Autodesk Fusion 360 part; units mm, degrees
(part 7 of 7)
equation "d681 = spokeDepth"
equation "d683 = bodyWidth"
equation "d684 = bodyLength"
equation "d687 = rootRadius"
equation "d688 = qFrontBack"
equation "d690 = rearCarrierClearance"
equation "d691 = spokeDepth"
equation "d693 = qFront"
equation "d695 = raceRelief"
equation "d696 = frontSeatDepth + shoulder"
equation "d698 = qFront"
equation "d700 = seatDiameter"
equation "d701 = frontSeatDepth"
equation "d703 = qFront"
equation "d705 = supportCircle / 2"
equation "d706 = m3Clearance"
equation "d707 = frontSeatDepth + shoulder"
equation "d711 = qFront"
equation "d713 = coreOD"
equation "d714 = entryChamfer"
equation "d715 = bodyWidth / 2"
equation "d717 = abs(( 16 mm + ( -6.5 mm ) ) / sqrt(2))"
equation "d718 = abs(( 16 mm - ( -6.5 mm ) ) / sqrt(2))"
equation "d720 = abs(( 16 mm + ( 6.5 mm ) ) / sqrt(2))"
equation "d721 = abs(( 16 mm - ( 6.5 mm ) ) / sqrt(2))"
equation "d723 = -( bodyWidth / 2 )"
equation "d725 = -qFront"
equation "d727 = mountOD"
equation "d728 = -( -qFront - hubFace )"
equation "d730 = -qFront"
equation "d732 = abs(( 0 mm ) * ( cos(-73.6750500631048 deg) ) - ( -1 ) * spokeWidth / 2 * ( sin(-73.6750500631048 deg) ))"
equation "d733 = abs(( 0 mm ) * ( sin(-73.6750500631048 deg) ) + ( -1 ) * spokeWidth / 2 * ( cos(-73.6750500631048 deg) ))"
equation "d734 = abs(( bodyWidth ) * ( cos(-73.6750500631048 deg) ) - ( -1 ) * spokeWidth / 2 * ( sin(-73.6750500631048 deg) ))"
equation "d735 = abs(( bodyWidth ) * ( sin(-73.6750500631048 deg) ) + ( -1 ) * spokeWidth / 2 * ( cos(-73.6750500631048 deg) ))"
equation "d736 = abs(( bodyWidth ) * ( cos(-73.6750500631048 deg) ) - ( 1 ) * spokeWidth / 2 * ( sin(-73.6750500631048 deg) ))"
equation "d737 = abs(( bodyWidth ) * ( sin(-73.6750500631048 deg) ) + ( 1 ) * spokeWidth / 2 * ( cos(-73.6750500631048 deg) ))"
equation "d738 = abs(( 0 mm ) * ( cos(-73.6750500631048 deg) ) - ( 1 ) * spokeWidth / 2 * ( sin(-73.6750500631048 deg) ))"
equation "d739 = abs(( 0 mm ) * ( sin(-73.6750500631048 deg) ) + ( 1 ) * spokeWidth / 2 * ( cos(-73.6750500631048 deg) ))"
equation "d740 = -( spokeDepth )"
equation "d742 = abs(( 0 mm ) * ( cos(-30.3611934048217 deg) ) - ( -1 ) * spokeWidth / 2 * ( sin(-30.3611934048217 deg) ))"
equation "d743 = abs(( 0 mm ) * ( sin(-30.3611934048217 deg) ) + ( -1 ) * spokeWidth / 2 * ( cos(-30.3611934048217 deg) ))"
equation "d744 = abs(( bodyWidth ) * ( cos(-30.3611934048217 deg) ) - ( -1 ) * spokeWidth / 2 * ( sin(-30.3611934048217 deg) ))"
equation "d745 = abs(( bodyWidth ) * ( sin(-30.3611934048217 deg) ) + ( -1 ) * spokeWidth / 2 * ( cos(-30.3611934048217 deg) ))"
equation "d746 = abs(( bodyWidth ) * ( cos(-30.3611934048217 deg) ) - ( 1 ) * spokeWidth / 2 * ( sin(-30.3611934048217 deg) ))"
equation "d747 = abs(( bodyWidth ) * ( sin(-30.3611934048217 deg) ) + ( 1 ) * spokeWidth / 2 * ( cos(-30.3611934048217 deg) ))"
equation "d748 = abs(( 0 mm ) * ( cos(-30.3611934048217 deg) ) - ( 1 ) * spokeWidth / 2 * ( sin(-30.3611934048217 deg) ))"
equation "d749 = abs(( 0 mm ) * ( sin(-30.3611934048217 deg) ) + ( 1 ) * spokeWidth / 2 * ( cos(-30.3611934048217 deg) ))"
equation "d750 = -( spokeDepth )"
equation "d752 = abs(( 0 mm ) * ( cos(30.3611934048217 deg) ) - ( -1 ) * spokeWidth / 2 * ( sin(30.3611934048217 deg) ))"
equation "d753 = abs(( 0 mm ) * ( sin(30.3611934048217 deg) ) + ( -1 ) * spokeWidth / 2 * ( cos(30.3611934048217 deg) ))"
equation "d754 = abs(( bodyWidth ) * ( cos(30.3611934048217 deg) ) - ( -1 ) * spokeWidth / 2 * ( sin(30.3611934048217 deg) ))"
equation "d755 = abs(( bodyWidth ) * ( sin(30.3611934048217 deg) ) + ( -1 ) * spokeWidth / 2 * ( cos(30.3611934048217 deg) ))"
equation "d756 = abs(( bodyWidth ) * ( cos(30.3611934048217 deg) ) - ( 1 ) * spokeWidth / 2 * ( sin(30.3611934048217 deg) ))"
equation "d757 = abs(( bodyWidth ) * ( sin(30.3611934048217 deg) ) + ( 1 ) * spokeWidth / 2 * ( cos(30.3611934048217 deg) ))"
equation "d758 = abs(( 0 mm ) * ( cos(30.3611934048217 deg) ) - ( 1 ) * spokeWidth / 2 * ( sin(30.3611934048217 deg) ))"
equation "d759 = abs(( 0 mm ) * ( sin(30.3611934048217 deg) ) + ( 1 ) * spokeWidth / 2 * ( cos(30.3611934048217 deg) ))"
equation "d760 = -( spokeDepth )"
equation "d762 = abs(( 0 mm ) * ( cos(73.6750500631048 deg) ) - ( -1 ) * spokeWidth / 2 * ( sin(73.6750500631048 deg) ))"
equation "d763 = abs(( 0 mm ) * ( sin(73.6750500631048 deg) ) + ( -1 ) * spokeWidth / 2 * ( cos(73.6750500631048 deg) ))"
equation "d764 = abs(( bodyWidth ) * ( cos(73.6750500631048 deg) ) - ( -1 ) * spokeWidth / 2 * ( sin(73.6750500631048 deg) ))"
equation "d765 = abs(( bodyWidth ) * ( sin(73.6750500631048 deg) ) + ( -1 ) * spokeWidth / 2 * ( cos(73.6750500631048 deg) ))"
equation "d766 = abs(( bodyWidth ) * ( cos(73.6750500631048 deg) ) - ( 1 ) * spokeWidth / 2 * ( sin(73.6750500631048 deg) ))"
equation "d767 = abs(( bodyWidth ) * ( sin(73.6750500631048 deg) ) + ( 1 ) * spokeWidth / 2 * ( cos(73.6750500631048 deg) ))"
equation "d768 = abs(( 0 mm ) * ( cos(73.6750500631048 deg) ) - ( 1 ) * spokeWidth / 2 * ( sin(73.6750500631048 deg) ))"
equation "d769 = abs(( 0 mm ) * ( sin(73.6750500631048 deg) ) + ( 1 ) * spokeWidth / 2 * ( cos(73.6750500631048 deg) ))"
equation "d770 = -( spokeDepth )"
equation "d772 = abs(( 0 mm ) * ( cos(106.324949936895 deg) ) - ( -1 ) * spokeWidth / 2 * ( sin(106.324949936895 deg) ))"
equation "d773 = abs(( 0 mm ) * ( sin(106.324949936895 deg) ) + ( -1 ) * spokeWidth / 2 * ( cos(106.324949936895 deg) ))"
equation "d774 = abs(( bodyWidth ) * ( cos(106.324949936895 deg) ) - ( -1 ) * spokeWidth / 2 * ( sin(106.324949936895 deg) ))"
equation "d775 = abs(( bodyWidth ) * ( sin(106.324949936895 deg) ) + ( -1 ) * spokeWidth / 2 * ( cos(106.324949936895 deg) ))"
equation "d776 = abs(( bodyWidth ) * ( cos(106.324949936895 deg) ) - ( 1 ) * spokeWidth / 2 * ( sin(106.324949936895 deg) ))"
equation "d777 = abs(( bodyWidth ) * ( sin(106.324949936895 deg) ) + ( 1 ) * spokeWidth / 2 * ( cos(106.324949936895 deg) ))"
equation "d778 = abs(( 0 mm ) * ( cos(106.324949936895 deg) ) - ( 1 ) * spokeWidth / 2 * ( sin(106.324949936895 deg) ))"
equation "d779 = abs(( 0 mm ) * ( sin(106.324949936895 deg) ) + ( 1 ) * spokeWidth / 2 * ( cos(106.324949936895 deg) ))"
equation "d780 = -( spokeDepth )"
equation "d782 = abs(( 0 mm ) * ( cos(149.638806595178 deg) ) - ( -1 ) * spokeWidth / 2 * ( sin(149.638806595178 deg) ))"
equation "d783 = abs(( 0 mm ) * ( sin(149.638806595178 deg) ) + ( -1 ) * spokeWidth / 2 * ( cos(149.638806595178 deg) ))"
equation "d784 = abs(( bodyWidth ) * ( cos(149.638806595178 deg) ) - ( -1 ) * spokeWidth / 2 * ( sin(149.638806595178 deg) ))"
equation "d785 = abs(( bodyWidth ) * ( sin(149.638806595178 deg) ) + ( -1 ) * spokeWidth / 2 * ( cos(149.638806595178 deg) ))"
equation "d786 = abs(( bodyWidth ) * ( cos(149.638806595178 deg) ) - ( 1 ) * spokeWidth / 2 * ( sin(149.638806595178 deg) ))"
equation "d787 = abs(( bodyWidth ) * ( sin(149.638806595178 deg) ) + ( 1 ) * spokeWidth / 2 * ( cos(149.638806595178 deg) ))"
equation "d788 = abs(( 0 mm ) * ( cos(149.638806595178 deg) ) - ( 1 ) * spokeWidth / 2 * ( sin(149.638806595178 deg) ))"
equation "d789 = abs(( 0 mm ) * ( sin(149.638806595178 deg) ) + ( 1 ) * spokeWidth / 2 * ( cos(149.638806595178 deg) ))"
equation "d790 = -( spokeDepth )"
equation "d792 = abs(( 0 mm ) * ( cos(-149.638806595178 deg) ) - ( -1 ) * spokeWidth / 2 * ( sin(-149.638806595178 deg) ))"
equation "d793 = abs(( 0 mm ) * ( sin(-149.638806595178 deg) ) + ( -1 ) * spokeWidth / 2 * ( cos(-149.638806595178 deg) ))"
equation "d794 = abs(( bodyWidth ) * ( cos(-149.638806595178 deg) ) - ( -1 ) * spokeWidth / 2 * ( sin(-149.638806595178 deg) ))"
equation "d795 = abs(( bodyWidth ) * ( sin(-149.638806595178 deg) ) + ( -1 ) * spokeWidth / 2 * ( cos(-149.638806595178 deg) ))"
equation "d796 = abs(( bodyWidth ) * ( cos(-149.638806595178 deg) ) - ( 1 ) * spokeWidth / 2 * ( sin(-149.638806595178 deg) ))"
equation "d797 = abs(( bodyWidth ) * ( sin(-149.638806595178 deg) ) + ( 1 ) * spokeWidth / 2 * ( cos(-149.638806595178 deg) ))"
equation "d798 = abs(( 0 mm ) * ( cos(-149.638806595178 deg) ) - ( 1 ) * spokeWidth / 2 * ( sin(-149.638806595178 deg) ))"
equation "d799 = abs(( 0 mm ) * ( sin(-149.638806595178 deg) ) + ( 1 ) * spokeWidth / 2 * ( cos(-149.638806595178 deg) ))"
equation "d800 = -( spokeDepth )"
equation "d802 = abs(( 0 mm ) * ( cos(-106.324949936895 deg) ) - ( -1 ) * spokeWidth / 2 * ( sin(-106.324949936895 deg) ))"
equation "d803 = abs(( 0 mm ) * ( sin(-106.324949936895 deg) ) + ( -1 ) * spokeWidth / 2 * ( cos(-106.324949936895 deg) ))"
equation "d804 = abs(( bodyWidth ) * ( cos(-106.324949936895 deg) ) - ( -1 ) * spokeWidth / 2 * ( sin(-106.324949936895 deg) ))"
equation "d805 = abs(( bodyWidth ) * ( sin(-106.324949936895 deg) ) + ( -1 ) * spokeWidth / 2 * ( cos(-106.324949936895 deg) ))"
equation "d806 = abs(( bodyWidth ) * ( cos(-106.324949936895 deg) ) - ( 1 ) * spokeWidth / 2 * ( sin(-106.324949936895 deg) ))"
equation "d807 = abs(( bodyWidth ) * ( sin(-106.324949936895 deg) ) + ( 1 ) * spokeWidth / 2 * ( cos(-106.324949936895 deg) ))"
equation "d808 = abs(( 0 mm ) * ( cos(-106.324949936895 deg) ) - ( 1 ) * spokeWidth / 2 * ( sin(-106.324949936895 deg) ))"
equation "d809 = abs(( 0 mm ) * ( sin(-106.324949936895 deg) ) + ( 1 ) * spokeWidth / 2 * ( cos(-106.324949936895 deg) ))"
equation "d810 = -( spokeDepth )"
equation "d812 = bodyWidth"
equation "d813 = bodyLength"
equation "d816 = rootRadius"
equation "d817 = -qFront"
equation "d819 = mountOpening"
equation "d820 = -( -qFront - hubFace )"
equation "d822 = -qFront"
equation "d824 = abs(mountCircle / ( 2 * sqrt(2) ))"
equation "d825 = abs(mountCircle / ( 2 * sqrt(2) ))"
equation "d826 = m4Clearance"
equation "d827 = abs(-mountCircle / ( 2 * sqrt(2) ))"
equation "d828 = abs(mountCircle / ( 2 * sqrt(2) ))"
equation "d829 = m4Clearance"
equation "d830 = abs(-mountCircle / ( 2 * sqrt(2) ))"
equation "d831 = abs(-mountCircle / ( 2 * sqrt(2) ))"
equation "d832 = m4Clearance"
equation "d833 = abs(mountCircle / ( 2 * sqrt(2) ))"
equation "d834 = abs(-mountCircle / ( 2 * sqrt(2) ))"
equation "d835 = m4Clearance"
equation "d836 = -( -qFront - hubFace )"
equation "d838 = abs(mountCircle / ( 2 * sqrt(2) ))"
equation "d839 = abs(mountCircle / ( 2 * sqrt(2) ))"
equation "d840 = 2 * ( nutAF ) / sqrt(3)"
equation "d841 = -( nutDepth )"
equation "d843 = abs(-mountCircle / ( 2 * sqrt(2) ))"
equation "d844 = abs(mountCircle / ( 2 * sqrt(2) ))"
equation "d845 = 2 * ( nutAF ) / sqrt(3)"
equation "d846 = -( nutDepth )"
equation "d848 = abs(-mountCircle / ( 2 * sqrt(2) ))"
equation "d849 = abs(-mountCircle / ( 2 * sqrt(2) ))"
equation "d850 = 2 * ( nutAF ) / sqrt(3)"
equation "d851 = -( nutDepth )"
equation "d853 = abs(mountCircle / ( 2 * sqrt(2) ))"
equation "d854 = abs(-mountCircle / ( 2 * sqrt(2) ))"
equation "d855 = 2 * ( nutAF ) / sqrt(3)"
equation "d856 = -( nutDepth )"
equation "d858 = abs(( -8 mm - 13 mm ) / sqrt(2))"
equation "d859 = abs(( -8 mm + 13 mm ) / sqrt(2))"
equation "d860 = abs(( -30 mm - 13 mm ) / sqrt(2))"
equation "d861 = abs(( -30 mm + 13 mm ) / sqrt(2))"
equation "d862 = abs(( -30 mm + 13 mm ) / sqrt(2))"
equation "d863 = abs(( -30 mm - 13 mm ) / sqrt(2))"
equation "d864 = abs(( -8 mm + 13 mm ) / sqrt(2))"
equation "d865 = abs(( -8 mm - 13 mm ) / sqrt(2))"
equation "d866 = mountOD"
equation "d868 = bedRelief"
equation "d869 = tubeCornerChamfer"
equation "d870 = tubeRimChamfer"
equation "d873 = bodyWidth / 2"
equation "d875 = abs(( 1 ) * ( ( 1 ) * cordStation ) + ( 0 ) * ( 0 mm ))"
equation "d877 = -( wall )"
equation "d879 = bedRelief"
equation "d882 = bodyWidth / 2"
equation "d884 = abs(( -1 ) * ( ( 1 ) * cordStation ) + ( 0 ) * ( 0 mm ))"
equation "d886 = -( wall )"
equation "d888 = bedRelief"
equation "d889 = bedRelief"
equation "d890 = tubeCornerChamfer"
equation "d891 = tubeRimChamfer"
equation "d894 = bodyWidth / 2"
equation "d896 = abs(( 1 ) * ( ( -1 ) * cordStation ) + ( 0 ) * ( 0 mm ))"
equation "d898 = -( wall )"
equation "d900 = bedRelief"
equation "d903 = bodyWidth / 2"
equation "d905 = abs(( -1 ) * ( ( -1 ) * cordStation ) + ( 0 ) * ( 0 mm ))"
equation "d907 = -( wall )"
equation "d909 = bedRelief"
equation "d910 = qRearBase"
equation "d912 = coreOD"
equation "d913 = shoulder + rearSeatDepth"
equation "d915 = qRearBase"
equation "d917 = raceRelief"
equation "d918 = shoulder + rearSeatDepth"
equation "d920 = qRearBearing"
equation "d922 = seatDiameter"
equation "d923 = rearSeatDepth"
equation "d925 = qRearBase"
equation "d927 = supportCircle / 2"
equation "d928 = m3Clearance"
equation "d929 = shoulder + rearSeatDepth"
equation "d933 = entryChamfer"
equation "d934 = bedRelief"
equation "d935 = qFront - capThickness"
equation "d937 = coreOD"
equation "d938 = raceRelief"
equation "d939 = capThickness"
equation "d941 = qFront - capThickness"
equation "d943 = supportCircle / 2"
equation "d944 = m3Clearance"
equation "d945 = capThickness"
equation "d949 = bedRelief"
equation "d950 = qRearEnd"
equation "d952 = coreOD"
equation "d953 = raceRelief"
equation "d954 = capThickness"
equation "d956 = qRearEnd"
equation "d958 = supportCircle / 2"
equation "d959 = m3Clearance"
equation "d960 = capThickness"
equation "d964 = bedRelief"
equation "d965 = hubFace - adapterThickness"
equation "d967 = mountOD"
equation "d968 = adapterThickness"
equation "d970 = hubFace"
equation "d972 = pilotDiameter"
equation "d973 = pilotInside"
equation "d974 = pilotHeight"
equation "d976 = hubFace - adapterThickness"
equation "d978 = shaftClearance"
equation "d979 = adapterThickness"
equation "d981 = hubFace - adapterThickness"
equation "d983 = abs(mountCircle / ( 2 * sqrt(2) ))"
equation "d984 = abs(mountCircle / ( 2 * sqrt(2) ))"
equation "d985 = m4Clearance"
equation "d986 = abs(-mountCircle / ( 2 * sqrt(2) ))"
equation "d987 = abs(mountCircle / ( 2 * sqrt(2) ))"
equation "d988 = m4Clearance"
equation "d989 = abs(-mountCircle / ( 2 * sqrt(2) ))"
equation "d990 = abs(-mountCircle / ( 2 * sqrt(2) ))"
equation "d991 = m4Clearance"
equation "d992 = abs(mountCircle / ( 2 * sqrt(2) ))"
equation "d993 = abs(-mountCircle / ( 2 * sqrt(2) ))"
equation "d994 = m4Clearance"
equation "d995 = adapterThickness"
equation "d997 = abs(hubHoleSpacing / sqrt(2))"
equation "d998 = sleeveOD + sleeveAllowance"
equation "d999 = abs(hubHoleSpacing / sqrt(2))"
equation "d1000 = sleeveOD + sleeveAllowance"
equation "d1001 = abs(-hubHoleSpacing / sqrt(2))"
equation "d1002 = sleeveOD + sleeveAllowance"
equation "d1003 = abs(-hubHoleSpacing / sqrt(2))"
equation "d1004 = sleeveOD + sleeveAllowance"
equation "d1005 = adapterThickness"
equation "d1007 = entryChamfer"
equation "d1008 = bedRelief"
named bodies: "A Housing print", "B Moving Body print"
